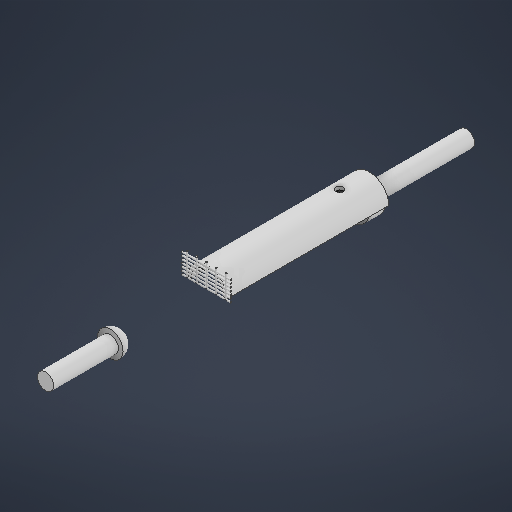
# Autodesk Inventor part: 10.2_first_stamp_method_sketch
Saved by Autodesk Inventor 2027.1 (Build 311270010, 270A)
## iProperties
Created: 2026-10-02
Part Number: 10.2_first_stamp_method_sketch
Material: Generic
Document SubType Name: Modeling
Designer: Seohyun_Lee
Density: 1 g/cm^3
Appearance: Default
Author: Seohyun_Lee
Autodesk Inventor part; units mm, degrees
ref_plane "YZ Plane" through (0, 0, 0) normal (1, 0, 0) x (0, 1, 0)
ref_plane "XZ Plane" through (0, 0, 0) normal (0, 1, 0) x (-1, 0, 0)
sketch "Sketch1" plane through (0, 0, 0) normal (0, 0, 1) x (1, 0, 0)
  arc A0 (50, 0) -> (-50, 0) centre (0, 0) ccw
  arc A1 (60, 0) -> (-60, 0) centre (0, 0) ccw
  line L0 (-60, 0) -> (-50, 0)
  line L1 (50, 0) -> (60, 0)
  dimension "d0" = 100
  dimension "d1" = 120
  constraints: 4 end point, 4 point on circle, 2 centre point, 2 coincident, 2 horizontal
  measures "d0" diameter of A0
  measures "d1" diameter of A1
extrude "Extrusion1" add sketch "Sketch1" along normal blind 500
sketch "Sketch3" plane through (0, 0, 0) normal (0, 0, 1) x (1, 0, 0)
  circle A0 centre (0, 0) radius 50
  dimension "d4" = 100
  constraints: 1 centre point, 1 coincident
  measures "d4" diameter of A0
extrude "Extrusion2" add sketch "Sketch3" along normal blind 50 separate body
sketch "Sketch5" plane through (0, 0, 50) normal (0, 0, 1) x (1, 0, 0)
  circle A0 centre (0, 0) radius 20
  dimension "d7" = 40
  constraints: 1 centre point, 1 coincident
  measures "d7" diameter of A0
extrude "Extrusion3" cut sketch "Sketch5" against normal blind 20 bodies 2
sketch "Sketch7" plane through (0, 0, 0) normal (0, 0, 1) x (1, 0, 0)
  circle A0 centre (0, 0) radius 25
  dimension "d10" = 50
  constraints: 1 centre point, 1 coincident
  measures "d10" diameter of A0
extrude "Extrusion4" add sketch "Sketch7" against normal blind 300 bodies 2
sketch "Sketch8" plane through (0, 0, 0) normal (1, 0, 0) x (0, 1, 0)
  circle A0 centre (0, 502.5) radius 2.5
  point P0 (0, 0)
  point P1 (0, 500)
  constraints: 1 centre point
extrude "Extrusion5" add sketch "Sketch8" along normal mid plane 150 separate body
pattern_linear "Rectangular Pattern1" count 7 spacing 10 along (0, 1, 0) of "Extrusion5" bodies 3
sketch "Sketch10" plane through (0, 0, 0) normal (0, 1, 0) x (-1, 0, 0)
  circle A0 centre (0, 502.5) radius 2.5
  line L0 (-50, 500) -> (50, 500) projected
  circle A1 centre (0, 502.5) radius 2.5
  point P0 (0, 0)
  dimension "d20" = 5
  dimension "d21" = 2.5
  constraints: 2 centre point, 1 coincident, 1 concentric
  measures "d20" diameter of A0
  measures "d21" distance from line of L0 A0.centre
extrude "Extrusion6" add sketch "Sketch10" along normal blind 70 separate body
pattern_linear "Rectangular Pattern2" count 5 spacing 30 along (-1, 0, 0) of "Extrusion6" first direction both ways yes bodies 4
ref_plane "Work Plane3" through (0, 0, 800) normal (0, 0, 1) x (1, 0, 0)
sketch "Sketch12" plane through (0, 0, 800) normal (0, 0, 1) x (1, 0, 0)
  circle A0 centre (0, 0) radius 25
  dimension "d28" = 50
  constraints: 1 centre point, 1 coincident
  measures "d28" diameter of A0
extrude "Extrusion7" add sketch "Sketch12" along normal blind 200 separate body
sketch "Sketch14" plane through (0, 0, 800) normal (0, 0, -1) x (-1, 0, 0)
  point P0 (0, 0)
sketch "Sketch15" plane through (0, 0, 800) normal (0, 0, -1) x (-1, 0, 0)
  arc A0 (39.3648, 0) -> (-39.3648, 0) centre (0, 0) ccw
  line L0 (0, 0) -> (39.3648, 0)
  line L1 (0, 0) -> (-39.3648, 0)
  constraints: 4 end point, 2 point on circle, 1 centre point, 1 coincident, 1 horizontal, 1 point on line
revolve "Revolution1" add sketch "Sketch15" angle 180 about axis through (0, 0, 800) along (-1, 0, 0) separate body
sketch "Sketch16" plane through (0, 0, 0) normal (0, 1, 0) x (-1, 0, 0)
  circle A0 centre (0, 92.3009) radius 11.9503
  point P0 (0, 0)
  constraints: 1 centre point
extrude "Extrusion8" cut sketch "Sketch16" along normal blind 200 bodies 1
body "Solid1"
body "Solid2"
body "Solid3"
body "Solid4"
body "Solid5"
body "Solid6"
